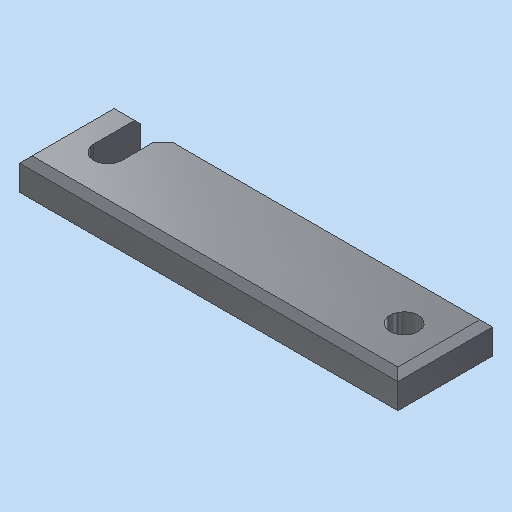
# Autodesk Inventor part: MM0948AN002_G01_108
Saved by Autodesk Inventor 2023.3 (Build 273359000, 359)
## iProperties
Created: 2023-03-23
Part Number: MM0948AN002_G01_108
Material: 3.3547 AlMg4,5Mn0,7 - AW 5083
Document SubType Name: Modeling
Designer: rat3an
Density: 2.7 g/cm^3
Appearance: Aluminium AnP
Description: =<RBPARTNOTITLE2>
Mass: 11.1402 g
Surface Area: 24.9332 cm^2
Volume: 4.12601 cm^3
RBMATERIAL: =<Material>
RBMATNO: =<Part Number>
RBPARTMADEOF: 5 x 15 x 60 (FM)
RBPARTNO: SIEHE MNR
RBPARTNOTITLE1: manufactured part
RBPARTNOTITLE2: Anfertigungsteil
AnP_Kommentar: farblos eloxiert
MaxAbmaße: 5 x 15 x 60 (FM)
AnP_Material_aktuell: =<Material>
AnP_Kommentar_aktuell: =<Comments>
RBDRAWINGMISSINGSPEC: --
RBSURFACE: anodised colourless
AnP_Kategorie: 1
RBSURFACE2: eloxiert farblos
AnP_Material: =<Material>
Author: FH/Wi
Keywords: =<RBPARTMADEOF>
Comments: =<RBSURFACE2>
Revision Number: 01
Autodesk Inventor part; units mm, degrees
ref_plane "YZ Plane" through (0, 0, 0) normal (1, 0, 0) x (0, 1, 0)
ref_plane "XZ Plane" through (0, 0, 0) normal (0, 1, 0) x (-1, 0, 0)
ref_plane "XY Plane" through (0, 0, 0) normal (0, 0, 1) x (1, 0, 0)
sketch "Skizze1" plane through (0, 0, 0) normal (0, 0, 1) x (1, 0, 0)
  line L0 (-30, 0) -> (30, 0)
  line L1 (30, 0) -> (30, 15)
  line L2 (30, 15) -> (-30, 15)
  line L3 (-30, 15) -> (-30, 0)
  line L4 (0, 18) -> (0, -3) projected
  line L5 (-42, 0) -> (42, 0) projected
  dimension "d0" = 15
  dimension "d1" = 60
  constraints: 8 end point, 3 parallel, 1 collinear, 1 horizontal, 1 perpendicular, 1 other
  measures "d0" distance between parallel lines of L0 L2
  measures "d1" distance between parallel lines of L3 L1
extrude "Extrusion1" add sketch "Skizze1" along normal blind 5
sketch "Skizze2" plane through (0, 0, 5) normal (0, 0, 1) x (1, 0, 0)
  line L0 (0, 18) -> (0, -3) projected
  line L1 (30, 15) -> (-30, 15) projected
  point P0 (-23.5, 7.5)
  point P1 (23.5, 7.5)
  dimension "d7" = 47
  dimension "d23" = 7.5
  constraints: 1 symmetric about line
  measures "d7" distance of point (23.5, 7.5) point (-23.5, 7.5)
  measures "d23" distance from line of L1 point (-23.5, 7.5)
hole "Bohrung1" at (-23.5, 7.5, 5) at (23.5, 7.5, 5) direction (0, 0, -1) diameter 4.5 end through all
sketch "Skizze3" plane through (0, 0, 5) normal (0, 0, 1) x (1, 0, 0)
  circle A0 centre (-23.5, 7.5) radius 2.25 projected
  line L0 (25.5, 13) -> (27.5, 15) projected
  line L1 (-25.75, 7.5) -> (-25.75, 15)
  line L2 (-21.25, 7.5) -> (-21.25, 12.5)
  line L3 (-21.25, 12.5) -> (-18.75, 15)
  line L4 (-18.75, 15) -> (-25.75, 15)
  circle A1 centre (-23.5, 7.5) radius 2.25 projected
  circle A2 centre (23.5, 7.5) radius 2.25 projected
  line L5 (-30, 0) -> (30, 0) projected
  line L6 (30, 0) -> (30, 15) projected
  line L7 (30, 15) -> (-30, 15) projected
  line L8 (-30, 15) -> (-30, 0) projected
  line L9 (30, 15) -> (-30, 15) projected
  dimension "d18" = 5
  dimension "d19" = 7.5
  dimension "d24" = 45
  constraints: 8 end point, 2 point on circle, 2 tangent, 1 collinear, 1 parallel, 1 perpendicular
  measures "d18" distance of L2.start L2.end
  measures "d19" distance of L1.start L1.end
  measures "d24" angle of L2 L3
extrude "Extrusion2" cut sketch "Skizze3" against normal blind 5 contours A0 L1 L4 L3 L2
chamfer "Fase2" distance 1 angle 45 5 edges at (-27.875, 15, 5) (5.625, 15, 5) (30, 7.5, 5) (0, 0, 5) (-30, 7.5, 5)
